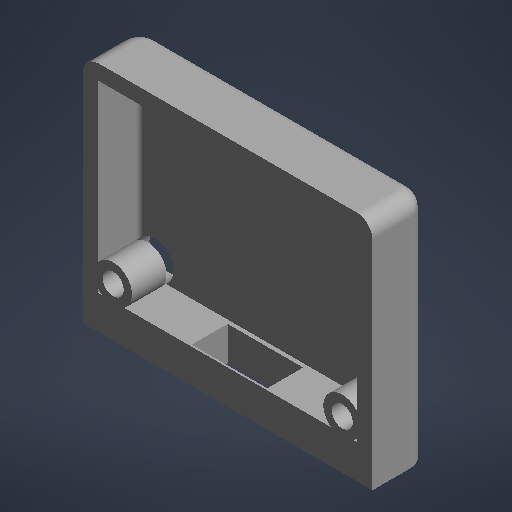
# Autodesk Inventor part: Cabeza_tapa
Saved by Autodesk Inventor 2027 (Build 310192060, 192F)
## iProperties
Part Number: Cabeza_tapa
Material: Genérico
Document SubType Name: Modelado
Designer: rodri
Appearance: Por defecto
Author: rodri
Autodesk Inventor part; units mm, degrees
sketch "Boceto1" plane through (0, 0, 0) normal (0, 1, 0) x (-1, 0, 0)
  line L0 (-23, -15) -> (23, -15)
  line L1 (23, -15) -> (23, 23)
  line L2 (23, 23) -> (-23, 23)
  line L3 (-23, 23) -> (-23, -15)
  constraints: 8 end point, 2 parallel, 1 horizontal, 1 perpendicular
extrude "Extrusión1" add sketch "Boceto1" against normal blind 37
fillet "Empalme1" radius 3 4 edges at (-23, -18.5, -15) (-23, -18.5, 23) (23, -18.5, 23) (23, -18.5, -15)
fillet "Empalme2" radius 2.5 8 edges at (22.1213, 0, -14.1213) (0, 0, -15) (22.1213, 0, 22.1213) (0, 0, 23) (-22.1213, 0, 22.1213) (-22.1213, 0, -14.1213) (-23, 0, 4) (23, 0, 4)
ref_plane "Plano de trabajo1" through (0, -2.4, 0) normal (0, 1, 0) x (-1, 0, 0)
sketch "Boceto2" plane through (0, -2.4, 0) normal (0, 1, 0) x (-1, 0, 0)
  line L0 (-20.6, -12.6) -> (20.6, -12.6)
  line L1 (20.6, -12.6) -> (20.6, 20.6)
  line L2 (20.6, 20.6) -> (-20.6, 20.6)
  line L3 (-20.6, 20.6) -> (-20.6, -12.6)
  constraints: 8 end point, 2 parallel, 1 horizontal, 1 perpendicular
extrude "Extrusión2" add sketch "Boceto2" against normal blind 29.2 separate body
fillet "Empalme3" radius 0.6 4 edges at (-20.6, -17, -12.6) (-20.6, -17, 20.6) (20.6, -17, 20.6) (20.6, -17, -12.6)
combine bodies "Combinar1" operation type subtract main body 1 bodies to subtract 2
ref_plane "Plano de trabajo2" through (0, 0, 23) normal (0, 0, 1) x (1, 0, 0)
sketch "Boceto3" plane through (0, 0, 23) normal (0, 0, 1) x (1, 0, 0)
  line L0 (-18, -28.5) -> (18, -28.5)
  line L1 (18, -28.5) -> (18, -7.5)
  line L2 (18, -7.5) -> (-18, -7.5)
  line L3 (-18, -7.5) -> (-18, -28.5)
  line L4 (-14, -26) -> (14, -26)
  line L5 (14, -26) -> (14, -10)
  line L6 (14, -10) -> (-14, -10)
  line L7 (-14, -10) -> (-14, -26)
  constraints: 16 end point, 4 parallel, 2 horizontal, 2 perpendicular
extrude "Extrusión3" add sketch "Boceto3" along normal blind 1.2 bodies 1
sketch "Boceto4" plane through (0, 0, 23) normal (0, 0, 1) x (1, 0, 0)
  line L0 (-12.5, -24.75) -> (12.5, -24.75)
  line L1 (12.5, -24.75) -> (12.5, -11.25)
  line L2 (12.5, -11.25) -> (-12.5, -11.25)
  line L3 (-12.5, -11.25) -> (-12.5, -24.75)
  constraints: 8 end point, 2 parallel, 1 horizontal, 1 perpendicular
extrude "Extrusión4" cut sketch "Boceto4" against normal blind 3.4 bodies 1
sketch "Boceto5" plane through (0, 0, 23) normal (0, 0, 1) x (1, 0, 0)
  line L0 (-8.8, -35) -> (-7.2, -35)
  line L1 (-7.2, -35) -> (-7.2, -31)
  line L2 (-7.2, -31) -> (-8.8, -31)
  line L3 (-8.8, -31) -> (-8.8, -35)
  line L4 (-4.8, -35) -> (-3.2, -35)
  line L5 (-3.2, -35) -> (-3.2, -31)
  line L6 (-3.2, -31) -> (-4.8, -31)
  line L7 (-4.8, -31) -> (-4.8, -35)
  line L8 (-0.8, -35) -> (0.8, -35)
  line L9 (0.8, -35) -> (0.8, -31)
  line L10 (0.8, -31) -> (-0.8, -31)
  line L11 (-0.8, -31) -> (-0.8, -35)
  line L12 (3.2, -35) -> (4.8, -35)
  line L13 (4.8, -35) -> (4.8, -31)
  line L14 (4.8, -31) -> (3.2, -31)
  line L15 (3.2, -31) -> (3.2, -35)
  line L16 (7.2, -35) -> (8.8, -35)
  line L17 (8.8, -35) -> (8.8, -31)
  line L18 (8.8, -31) -> (7.2, -31)
  line L19 (7.2, -31) -> (7.2, -35)
  constraints: 40 end point, 10 parallel, 5 horizontal, 5 perpendicular
extrude "Extrusión5" cut sketch "Boceto5" against normal blind 0.8 bodies 1
sketch "Boceto6" plane through (0, 0, 23) normal (0, 0, 1) x (1, 0, 0)
  circle A0 centre (19.5, -4) radius 1.2
  circle A1 centre (19.5, -33) radius 1.2
  circle A2 centre (-19.5, -4) radius 1.2
  circle A3 centre (-19.5, -33) radius 1.2
  constraints: 4 centre point
extrude "Extrusión6" add sketch "Boceto6" along normal blind 0.7 bodies 1
ref_plane "Plano de trabajo3" through (0, -37, 0) normal (0, 1, 0) x (-1, 0, 0)
sketch "Boceto7" plane through (0, -37, 0) normal (0, 1, 0) x (-1, 0, 0)
  circle A0 centre (0, 0) radius 3
  constraints: 1 centre point
extrude "Extrusión7" cut sketch "Boceto7" along normal blind 6.4 bodies 1
sketch "Boceto8" plane through (0, -37, 0) normal (0, 1, 0) x (-1, 0, 0)
  line L0 (-3.75, 0) -> (-3.7179, -0.4895)
  line L1 (-3.7179, -0.4895) -> (-3.6222, -0.9706)
  line L2 (-3.6222, -0.9706) -> (-3.4645, -1.4351)
  line L3 (-3.4645, -1.4351) -> (-3.2476, -1.875)
  line L4 (-3.2476, -1.875) -> (-2.9751, -2.2829)
  line L5 (-2.9751, -2.2829) -> (-2.6517, -2.6517)
  line L6 (-2.6517, -2.6517) -> (-2.2829, -2.9751)
  line L7 (-2.2829, -2.9751) -> (-1.875, -3.2476)
  line L8 (-1.875, -3.2476) -> (-1.4351, -3.4645)
  line L9 (-1.4351, -3.4645) -> (-0.9706, -3.6222)
  line L10 (-0.9706, -3.6222) -> (-0.4895, -3.7179)
  line L11 (-0.4895, -3.7179) -> (0, -3.75)
  line L12 (0, -3.75) -> (0.4895, -3.7179)
  line L13 (0.4895, -3.7179) -> (0.9706, -3.6222)
  line L14 (0.9706, -3.6222) -> (1.4351, -3.4645)
  line L15 (1.4351, -3.4645) -> (1.875, -3.2476)
  line L16 (1.875, -3.2476) -> (2.2829, -2.9751)
  line L17 (2.2829, -2.9751) -> (2.6517, -2.6517)
  line L18 (2.6517, -2.6517) -> (2.9751, -2.2829)
  line L19 (2.9751, -2.2829) -> (3.2476, -1.875)
  line L20 (3.2476, -1.875) -> (3.4645, -1.4351)
  line L21 (3.4645, -1.4351) -> (3.6222, -0.9706)
  line L22 (3.6222, -0.9706) -> (3.7179, -0.4895)
  line L23 (3.7179, -0.4895) -> (3.75, 0)
  line L24 (3.75, 0) -> (3.7179, 0.4895)
  line L25 (3.7179, 0.4895) -> (2.4, 15.95)
  line L26 (2.4, 15.95) -> (2.3182, 16.5712)
  line L27 (2.3182, 16.5712) -> (2.0785, 17.15)
  line L28 (2.0785, 17.15) -> (1.6971, 17.6471)
  line L29 (1.6971, 17.6471) -> (1.2, 18.0285)
  line L30 (1.2, 18.0285) -> (0.6212, 18.2682)
  line L31 (0.6212, 18.2682) -> (0, 18.35)
  line L32 (0, 18.35) -> (-0.6212, 18.2682)
  line L33 (-0.6212, 18.2682) -> (-1.2, 18.0285)
  line L34 (-1.2, 18.0285) -> (-1.6971, 17.6471)
  line L35 (-1.6971, 17.6471) -> (-2.0785, 17.15)
  line L36 (-2.0785, 17.15) -> (-2.3182, 16.5712)
  line L37 (-2.3182, 16.5712) -> (-2.4, 15.95)
  line L38 (-2.4, 15.95) -> (-3.7179, 0.4895)
  line L39 (-3.7179, 0.4895) -> (-3.75, 0)
  constraints: 80 end point
extrude "Extrusión8" cut sketch "Boceto8" along normal blind 2.4 bodies 1
sketch "Boceto9" plane through (0, -37, 0) normal (0, 1, 0) x (-1, 0, 0)
  circle A0 centre (0, 8.08) radius 0.6
  circle A1 centre (0, 12.02) radius 0.6
  constraints: 2 centre point
extrude "Extrusión9" cut sketch "Boceto9" along normal blind 5 bodies 1
ref_plane "Plano de trabajo4" through (23, 0, 0) normal (1, 0, 0) x (0, 1, 0)
sketch "Boceto10" plane through (23, 0, 0) normal (1, 0, 0) x (0, 1, 0)
  circle A0 centre (-18, 4) radius 6
  constraints: 1 centre point
extrude "Extrusión10" add sketch "Boceto10" along normal blind 2 bodies 1
ref_plane "Plano de trabajo5" through (25, 0, 0) normal (1, 0, 0) x (0, 1, 0)
sketch "Boceto11" plane through (25, 0, 0) normal (1, 0, 0) x (0, 1, 0)
  circle A0 centre (-18, 4) radius 3.5
  circle A1 centre (-18, 4) radius 1.5
  constraints: 2 centre point
extrude "Extrusión11" cut sketch "Boceto11" against normal blind 1 bodies 1
ref_plane "Plano de trabajo6" through (-23, 0, 0) normal (1, 0, 0) x (0, 1, 0)
sketch "Boceto12" plane through (-23, 0, 0) normal (1, 0, 0) x (0, 1, 0)
  circle A0 centre (-18, 4) radius 6
  constraints: 1 centre point
extrude "Extrusión12" add sketch "Boceto12" against normal blind 2 bodies 1
ref_plane "Plano de trabajo7" through (-25, 0, 0) normal (1, 0, 0) x (0, 1, 0)
sketch "Boceto13" plane through (-25, 0, 0) normal (1, 0, 0) x (0, 1, 0)
  circle A0 centre (-18, 4) radius 3.5
  circle A1 centre (-18, 4) radius 1.5
  constraints: 2 centre point
extrude "Extrusión13" cut sketch "Boceto13" along normal blind 1 bodies 1
ref_plane "Plano de trabajo8" through (0, 0, -6) normal (0, 0, 1) x (1, 0, 0)
sketch "Boceto14" plane through (0, 0, -6) normal (0, 0, 1) x (1, 0, 0)
  line L0 (-46, -74) -> (46, -74)
  line L1 (46, -74) -> (46, 37)
  line L2 (46, 37) -> (-46, 37)
  line L3 (-46, 37) -> (-46, -74)
  constraints: 8 end point, 2 parallel, 1 horizontal, 1 perpendicular
extrude "Extrusión14" cut sketch "Boceto14" along normal blind 38 bodies 1
ref_plane "Plano de trabajo9" through (0, 0, -6) normal (0, 0, 1) x (1, 0, 0)
sketch "Boceto15" plane through (0, 0, -6) normal (0, 0, 1) x (1, 0, 0)
  circle A0 centre (18.2, -29.2) radius 3
  circle A1 centre (-18.2, -29.2) radius 3
  constraints: 2 centre point
extrude "Extrusión15" add sketch "Boceto15" against normal blind 5.5 bodies 1
ref_plane "Plano de trabajo10" through (0, 0, -16) normal (0, 0, 1) x (1, 0, 0)
sketch "Boceto16" plane through (0, 0, -16) normal (0, 0, 1) x (1, 0, 0)
  circle A0 centre (18.2, -29.2) radius 1.7
  circle A1 centre (-18.2, -29.2) radius 1.7
  constraints: 2 centre point
extrude "Extrusión16" cut sketch "Boceto16" along normal blind 38 bodies 1
ref_plane "Plano de trabajo11" through (0, 0, -16) normal (0, 0, 1) x (1, 0, 0)
sketch "Boceto17" plane through (0, 0, -16) normal (0, 0, 1) x (1, 0, 0)
  circle A0 centre (18.2, -29.2) radius 3
  circle A1 centre (-18.2, -29.2) radius 3
  constraints: 2 centre point
extrude "Extrusión17" cut sketch "Boceto17" along normal blind 4 bodies 1
sketch "Boceto18" plane through (0, -37, 0) normal (0, 1, 0) x (-1, 0, 0)
  line L0 (-6, -12) -> (6, -12)
  line L1 (6, -12) -> (6, -6.3)
  line L2 (6, -6.3) -> (-6, -6.3)
  line L3 (-6, -6.3) -> (-6, -12)
  constraints: 8 end point, 2 parallel, 1 horizontal, 1 perpendicular
extrude "Extrusión18" cut sketch "Boceto18" along normal blind 6.4 bodies 1
